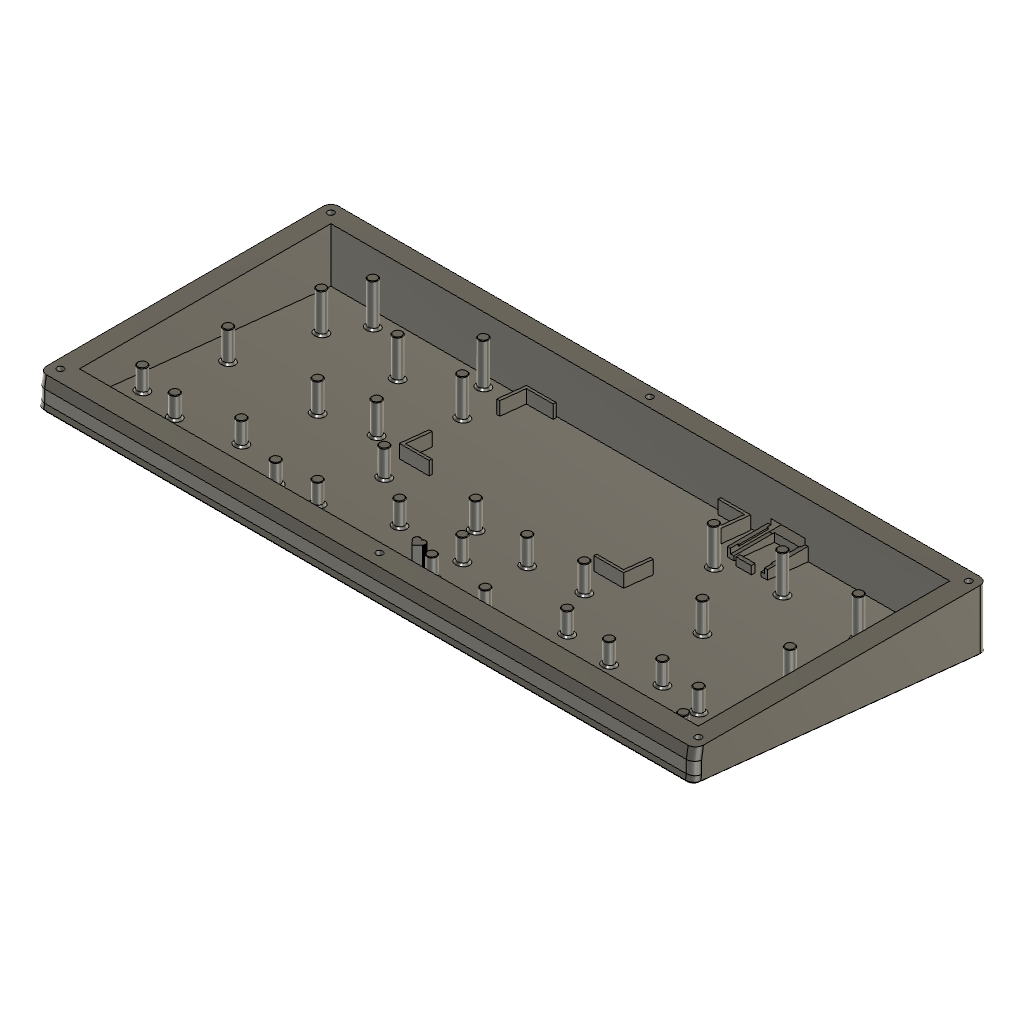
Bottom (Autodesk Fusion 360 design; units mm, degrees)
part number: 2026-11-25-15-39-00-303
part number: 2026-11-25-15-39-00-644
Autodesk Fusion 360 part; units mm, degrees
ref_plane "WorkPlane1" through (-10, 0, 0) normal (1, 0, 0) x (0, 1, 0) in component "Bottom"
sketch "side_profile" plane through (-10, 0, 0) normal (1, 0, 0) x (0, 0, -1) in component "Bottom"
  line L0 (-10, 10) -> (22.475, 10)
  line L1 (22.475, 10) -> (6.195, -144.863)
  line L2 (6.195, -144.863) -> (2.5, -144.25)
  line L3 (2.5, -144.25) -> (-4, -144.25)
  line L4 (-4, -144.25) -> (-10, -143.32)
  line L5 (-10, -143.32) -> (-10, 10)
extrude "Extrude1" add sketch "side_profile" along normal blind 344.85 makes body 1 in component "Bottom"
ref_plane "WorkPlane2" through (0, 0, -30) normal (0, 0, 1) x (1, 0, 0) in component "Bottom"
sketch "plan_outline" plane through (0, 0, -30) normal (0, 0, 1) x (1, 0, 0) in component "Bottom"
  line L0 (-10, -150) -> (334.85, -150)
  line L1 (334.85, -150) -> (334.85, 10)
  line L2 (334.85, 10) -> (-10, 10)
  line L3 (-10, 10) -> (-10, -150)
extrude "Extrude2" add sketch "plan_outline" along normal blind 50 separate body makes body 2 in component "Bottom"
fillet "Fillet1" radius 4 4 edges at (-10, 10, -5) (334.85, 10, -5) (334.85, -150, -5) (-10, -150, -5) on bodies 2 in component "Bottom"
combine "Combine1" operation intersect target body 1 tool bodies 2 in component "Bottom"
fillet "Front corner radius" radius 4 6 edges at (-10, -144.5565, -4.3475) (-10, -144.25, 0.75) (-10, -143.785, 7) (334.85, -144.5565, -4.3475) (334.85, -144.25, 0.75) (334.85, -143.785, 7) on bodies 1 in component "Bottom"
chamfer "Bottom edge chamfer" distance 1 angle 45 8 edges at (333.6784, -143.6958, -6.3177) (334.85, -67.4389, -14.3342) (333.6784, 8.8284, -22.3518) (162.425, 10, -22.475) (-8.8284, 8.8284, -22.3518) (-10, -67.4389, -14.3342) (-8.8284, -143.6958, -6.3177) (162.425, -144.863, -6.195) on bodies 1 in component "Bottom"
ref_plane "WorkPlane3" through (0, 0, 0) normal (1, 0, 0) x (0, 1, 0) in component "Bottom"
sketch "cavity_profile" plane through (0, 0, 0) normal (1, 0, 0) x (0, 0, -1) in component "Bottom"
  line L0 (-12, 0) -> (18.4216, 0)
  line L1 (18.4216, 0) -> (4.5516, -131.97)
  line L2 (4.5516, -131.97) -> (-12, -131.97)
  line L3 (-12, -131.97) -> (-12, 0)
extrude "Extrude3" cut sketch "cavity_profile" along normal blind 324.85 bodies 1 in component "Bottom"
ref_plane "WorkPlane4" through (0, 0, 10) normal (0, 0, 1) x (1, 0, 0) in component "Bottom"
sketch "screw_holes" plane through (0, 0, 10) normal (0, 0, 1) x (1, 0, 0) in component "Bottom"
  circle A0 centre (-5, 5) radius 1.7
  circle A1 centre (162.43, 5) radius 1.7
  circle A2 centre (329.85, 5) radius 1.7
  circle A3 centre (-5, -136.97) radius 1.7
  circle A4 centre (162.43, -136.97) radius 1.7
  circle A5 centre (329.85, -136.97) radius 1.7
  dimension "d27" = 3.4
  dimension "d28" = 3.4
  dimension "d29" = 3.4
  dimension "d30" = 3.4
  dimension "d31" = 3.4
  dimension "d32" = 3.4
  measures "d27" diameter of A0
  measures "d28" diameter of A1
  measures "d29" diameter of A2
  measures "d30" diameter of A3
  measures "d31" diameter of A4
  measures "d32" diameter of A5
ref_plane "WorkPlane5" through (0, 0, -3.7) normal (0, 0, 1) x (1, 0, 0) in component "Bottom"
sketch "counterbores_front" plane through (0, 0, -3.7) normal (0, 0, 1) x (1, 0, 0) in component "Bottom"
  circle A0 centre (-5, -136.97) radius 3
  circle A1 centre (162.43, -136.97) radius 3
  circle A2 centre (329.85, -136.97) radius 3
  dimension "d36" = 6
  dimension "d37" = 6
  dimension "d38" = 6
  measures "d36" diameter of A0
  measures "d37" diameter of A1
  measures "d38" diameter of A2
extrude "Counterbore front" cut sketch "counterbores_front" against normal blind 15 bodies 1 in component "Bottom"
ref_plane "WorkPlane6" through (0, 0, -17) normal (0, 0, 1) x (1, 0, 0) in component "Bottom"
sketch "counterbores_back" plane through (0, 0, -17) normal (0, 0, 1) x (1, 0, 0) in component "Bottom"
  circle A0 centre (-5, 5) radius 3
  circle A1 centre (162.43, 5) radius 3
  circle A2 centre (329.85, 5) radius 3
  dimension "d42" = 6
  dimension "d43" = 6
  dimension "d44" = 6
  measures "d42" diameter of A0
  measures "d43" diameter of A1
  measures "d44" diameter of A2
extrude "Counterbore back" cut sketch "counterbores_back" against normal blind 15 bodies 1 in component "Bottom"
sketch "foot_recesses" plane through (0, -2.2276, -21.1896) normal (0, -0.1045, -0.9945) x (0, 0.9945, -0.1045) in component "Bottom"
  circle A0 centre (-127.3101, 16) radius 6.665
  circle A1 centre (-3.6022, 16) radius 6.665
  circle A2 centre (-127.3101, 308.85) radius 6.665
  circle A3 centre (-3.6022, 308.85) radius 6.665
  ellipse E0 centre (-135.4849, 329.85) end of major axis (-138.5015, 329.85) minor radius 3
  ellipse E1 centre (-135.4849, 162.43) end of major axis (-138.5015, 162.43) minor radius 3
  ellipse E2 centre (-135.4849, -5) end of major axis (-138.5015, -5) minor radius 3
  ellipse E3 centre (7.2674, 329.85) end of major axis (4.2509, 329.85) minor radius 3
  ellipse E4 centre (7.2674, 162.43) end of major axis (4.2509, 162.43) minor radius 3
  ellipse E5 centre (7.2674, -5) end of major axis (4.2509, -5) minor radius 3
  line L0 (-139.3546, -9) -> (8.1678, -9)
  line L1 (8.2729, -9) -> (8.1678, -9)
  spline S0 degree 3 poles (11.2949, -6) (11.2949, -6.4845) (11.1745, -6.9686) (10.8063, -7.6628) (10.6252, -7.907) (10.4117, -8.1194) (10.1982, -8.3317) (9.9523, -8.5121) (9.2521, -8.8794) (8.7627, -9) (8.2729, -9) knots 0 0 0 0 0.485394 0.485394 0.785398 0.785398 0.785398 1.085403 1.085403 1.570796 1.570796 1.570796 1.570796
  line L2 (11.2949, -6) -> (11.2949, 330.85)
  spline S1 degree 3 poles (8.2729, 333.85) (8.7627, 333.85) (9.2521, 333.7294) (9.9523, 333.3621) (10.1982, 333.1817) (10.4117, 332.9694) (10.6252, 332.757) (10.8063, 332.5128) (11.1745, 331.8186) (11.2949, 331.3345) (11.2949, 330.85) knots -1.570796 -1.570796 -1.570796 -1.570796 -1.085403 -1.085403 -0.785398 -0.785398 -0.785398 -0.485394 -0.485394 0 0 0 0
  line L3 (8.1678, 333.85) -> (8.2729, 333.85)
  line L4 (8.1678, 333.85) -> (-139.3546, 333.85)
  line L5 (-139.4143, 333.85) -> (-139.3546, 333.85)
  spline S2 degree 3 poles (-142.4214, 330.85) (-142.4214, 331.3351) (-142.3012, 331.8198) (-141.9342, 332.5143) (-141.7539, 332.7585) (-141.5413, 332.9707) (-141.3287, 333.1829) (-141.084, 333.363) (-140.3875, 333.7298) (-139.9011, 333.85) (-139.4143, 333.85) knots 0 0 0 0 0.485398 0.485398 0.785398 0.785398 0.785398 1.085399 1.085399 1.570796 1.570796 1.570796 1.570796
  line L6 (-142.4214, 330.85) -> (-142.4214, -6)
  spline S3 degree 3 poles (-139.4143, -9) (-139.9011, -9) (-140.3875, -8.8798) (-141.084, -8.513) (-141.3287, -8.3329) (-141.5413, -8.1207) (-141.7539, -7.9085) (-141.9342, -7.6643) (-142.3012, -6.9698) (-142.4214, -6.4851) (-142.4214, -6) knots -1.570796 -1.570796 -1.570796 -1.570796 -1.085399 -1.085399 -0.785398 -0.785398 -0.785398 -0.485398 -0.485398 0 0 0 0
  line L7 (-139.3546, -9) -> (-139.4143, -9)
  dimension "d46" = 13.33
  dimension "d47" = 13.33
  dimension "d48" = 13.33
  dimension "d49" = 13.33
  measures "d46" diameter of A0
  measures "d47" diameter of A1
  measures "d48" diameter of A2
  measures "d49" diameter of A3
extrude "Extrude7" cut sketch "foot_recesses" against normal blind 1 contours A0 | A1 | A2 | A3 bodies 1 in component "Bottom"
ref_plane "WorkPlane7" through (0, 0, 5) normal (0, 0, 1) x (1, 0, 0) in component "Bottom"
sketch "support_posts" plane through (0, 0, 5) normal (0, 0, 1) x (1, 0, 0) in component "Bottom"
  circle A0 centre (170.5, -101.469) radius 2.5
  circle A1 centre (307.501, -66.469) radius 2.5
  circle A2 centre (30.501, -112.469) radius 2.5
  circle A3 centre (261.501, -24.469) radius 2.5
  circle A4 centre (301.501, -24.469) radius 2.5
  circle A5 centre (109.501, -81.469) radius 2.5
  circle A6 centre (309.501, -124.469) radius 2.5
  circle A7 centre (231.5, -30.469) radius 2.5
  circle A8 centre (97.501, -28.469) radius 2.5
  circle A9 centre (87.501, -116.469) radius 2.5
  circle A10 centre (107.501, -114.469) radius 2.5
  circle A11 centre (86.501, -62.469) radius 2.5
  circle A12 centre (9.501, -108.469) radius 2.5
  circle A13 centre (30.501, -8.469) radius 2.5
  circle A14 centre (187.501, -84.469) radius 2.5
  circle A15 centre (86.501, -6.469) radius 2.5
  circle A16 centre (231.501, -107.469) radius 2.5
  circle A17 centre (301.501, -108.469) radius 2.5
  circle A18 centre (21.501, -26.469) radius 2.5
  circle A19 centre (279.501, -105.469) radius 2.5
  circle A20 centre (171.501, -118.469) radius 2.5
  circle A21 centre (61.501, -68.469) radius 2.5
  circle A22 centre (137.5, -101.469) radius 2.5
  circle A23 centre (214.5, -81.469) radius 2.5
  circle A24 centre (62.501, -27.469) radius 2.5
  circle A25 centre (262.501, -67.469) radius 2.5
  circle A26 centre (14.501, -68.469) radius 2.5
  circle A27 centre (200.5, -119.469) radius 2.5
  circle A28 centre (59.501, -106.469) radius 2.5
  circle A29 centre (256.501, -110.469) radius 2.5
  circle A30 centre (157.501, -81.469) radius 2.5
  line L0 (162.501, -119.911) -> (159.835, -117.119)
  line L1 (159.835, -117.119) -> (159.647, -116.885)
  line L2 (159.647, -116.885) -> (159.502, -116.623)
  line L3 (159.502, -116.623) -> (159.404, -116.339)
  line L4 (159.404, -116.339) -> (159.356, -116.043)
  line L5 (159.356, -116.043) -> (159.359, -115.743)
  line L6 (159.359, -115.743) -> (159.413, -115.448)
  line L7 (159.413, -115.448) -> (159.516, -115.167)
  line L8 (159.516, -115.167) -> (159.667, -114.907)
  line L9 (159.667, -114.907) -> (159.859, -114.677)
  line L10 (159.859, -114.677) -> (160.088, -114.483)
  line L11 (160.088, -114.483) -> (160.346, -114.331)
  line L12 (160.346, -114.331) -> (160.627, -114.226)
  line L13 (160.627, -114.226) -> (160.764, -114.2)
  line L14 (160.764, -114.2) -> (160.922, -114.17)
  line L15 (160.922, -114.17) -> (161.222, -114.165)
  line L16 (161.222, -114.165) -> (161.518, -114.211)
  line L17 (161.518, -114.211) -> (161.802, -114.307)
  line L18 (161.802, -114.307) -> (161.943, -114.384)
  line L19 (161.943, -114.384) -> (162.066, -114.45)
  line L20 (162.066, -114.45) -> (162.301, -114.637)
  line L21 (162.301, -114.637) -> (162.501, -114.86)
  line L22 (162.501, -114.86) -> (162.7, -114.637)
  line L23 (162.7, -114.637) -> (162.935, -114.45)
  line L24 (162.935, -114.45) -> (163.058, -114.384)
  line L25 (163.058, -114.384) -> (163.199, -114.307)
  line L26 (163.199, -114.307) -> (163.483, -114.211)
  line L27 (163.483, -114.211) -> (163.779, -114.165)
  line L28 (163.779, -114.165) -> (164.079, -114.17)
  line L29 (164.079, -114.17) -> (164.237, -114.2)
  line L30 (164.237, -114.2) -> (164.374, -114.226)
  line L31 (164.374, -114.226) -> (164.655, -114.331)
  line L32 (164.655, -114.331) -> (164.913, -114.483)
  line L33 (164.913, -114.483) -> (165.142, -114.677)
  line L34 (165.142, -114.677) -> (165.334, -114.907)
  line L35 (165.334, -114.907) -> (165.414, -115.045)
  line L36 (165.414, -115.045) -> (165.485, -115.167)
  line L37 (165.485, -115.167) -> (165.588, -115.448)
  line L38 (165.588, -115.448) -> (165.643, -115.743)
  line L39 (165.643, -115.743) -> (165.645, -116.043)
  line L40 (165.645, -116.043) -> (165.597, -116.339)
  line L41 (165.597, -116.339) -> (165.499, -116.623)
  line L42 (165.499, -116.623) -> (165.354, -116.885)
  line L43 (165.354, -116.885) -> (165.166, -117.119)
  line L44 (165.166, -117.119) -> (162.501, -119.911)
  dimension "d58" = 5
  dimension "d59" = 5
  dimension "d60" = 5
  dimension "d61" = 5
  dimension "d62" = 5
  dimension "d63" = 5
  dimension "d64" = 5
  dimension "d65" = 5
  dimension "d66" = 5
  dimension "d67" = 5
  dimension "d68" = 5
  dimension "d69" = 5
  dimension "d70" = 5
  dimension "d71" = 5
  dimension "d72" = 5
  dimension "d73" = 5
  dimension "d74" = 5
  dimension "d75" = 5
  dimension "d76" = 5
  dimension "d77" = 5
  dimension "d78" = 5
  dimension "d79" = 5
  dimension "d80" = 5
  dimension "d81" = 5
  dimension "d82" = 5
  dimension "d83" = 5
  dimension "d84" = 5
  dimension "d85" = 5
  dimension "d86" = 5
  dimension "d87" = 5
  dimension "d88" = 5
  measures "d58" diameter of A0
  measures "d59" diameter of A1
  measures "d60" diameter of A2
  measures "d61" diameter of A3
  measures "d62" diameter of A4
  measures "d63" diameter of A5
  measures "d64" diameter of A6
  measures "d65" diameter of A7
  measures "d66" diameter of A8
  measures "d67" diameter of A9
  measures "d68" diameter of A10
  measures "d69" diameter of A11
  measures "d70" diameter of A12
  measures "d71" diameter of A13
  measures "d72" diameter of A14
  measures "d73" diameter of A15
  measures "d74" diameter of A16
  measures "d75" diameter of A17
  measures "d76" diameter of A18
  measures "d77" diameter of A19
  measures "d78" diameter of A20
  measures "d79" diameter of A21
  measures "d80" diameter of A22
  measures "d81" diameter of A23
  measures "d82" diameter of A24
  measures "d83" diameter of A25
  measures "d84" diameter of A26
  measures "d85" diameter of A27
  measures "d86" diameter of A28
  measures "d87" diameter of A29
  measures "d88" diameter of A30
extrude "Posts" add sketch "support_posts" along normal up to surface end surface through (0, 0, -18.4216) normal (0, 0.104524, 0.994522) offset 0 bodies 1 in component "Bottom"
chamfer "Post top chamfer" distance 0.3 angle 45 31 edges at (254.1702, -111.373, 5) (198.1692, -120.373, 5) (260.1702, -68.373, 5) (212.1692, -82.373, 5) (59.1702, -69.373, 5) (277.1702, -106.373, 5) (299.1702, -109.373, 5) (168.1692, -102.373, 5) (185.1702, -85.373, 5) (7.1702, -109.373, 5) (105.1702, -115.373, 5) (95.1702, -29.373, 5) (307.1702, -125.373, 5) (299.1702, -25.373, 5) (28.1702, -113.373, 5) (305.1702, -67.373, 5) (259.1702, -25.373, 5) (107.1702, -82.373, 5) (229.1692, -31.373, 5) (85.1702, -117.373, 5) (84.1702, -63.373, 5) (28.1702, -9.373, 5) (84.1702, -7.373, 5) (229.1702, -108.373, 5) (19.1702, -27.373, 5) (169.1702, -119.373, 5) (135.1692, -102.373, 5) (60.1702, -28.373, 5) (12.1702, -69.373, 5) (57.1702, -107.373, 5) (155.1702, -82.373, 5) on bodies 1 in component "Bottom"
chamfer "Post base chamfer" distance 1 angle 45 31 edges at (157.501, -78.969, -10.122) (59.501, -103.969, -7.4945) (14.501, -65.969, -11.4883) (62.501, -24.969, -15.7974) (137.5, -98.969, -8.02) (171.501, -115.969, -6.2333) (21.501, -23.969, -15.9025) (231.501, -104.969, -7.3894) (86.501, -3.969, -18.0045) (30.501, -5.969, -17.7943) (86.501, -59.969, -12.1189) (87.501, -113.969, -6.4435) (231.5, -27.969, -15.4821) (109.501, -78.969, -10.122) (261.501, -21.969, -16.1127) (307.501, -63.969, -11.6985) (30.501, -109.969, -6.8639) (301.501, -21.969, -16.1127) (309.501, -121.969, -5.6027) (97.501, -25.969, -15.6923) (107.501, -111.969, -6.6537) (9.501, -105.969, -7.2843) (187.501, -81.969, -9.8067) (170.5, -98.969, -8.02) (301.501, -105.969, -7.2843) (279.501, -102.969, -7.5996) (61.501, -65.969, -11.4883) (214.5, -78.969, -10.122) (262.501, -64.969, -11.5934) (200.5, -116.969, -6.1282) (256.501, -107.969, -7.0741) on bodies 1 in component "Bottom"
ref_plane "WorkPlane8" through (162.425, -65.2533, -4.5249) normal (0, 0.1045, 0.9945) x (0, -0.9945, 0.1045) in component "Bottom"
ref_plane "WorkPlane9" through (0, 0, -14) normal (0, 0, 1) x (1, 0, 0) in component "Bottom"
sketch "charger_rails" plane through (0, 0, -14) normal (0, 0, 1) x (1, 0, 0) in component "Bottom"
  line L0 (231.05, -21.3) -> (232.85, -21.3)
  line L1 (232.85, -21.3) -> (232.85, 0.5)
  line L2 (232.85, 0.5) -> (231.05, 0.5)
  line L3 (231.05, 0.5) -> (231.05, -21.3)
  line L4 (247.15, -21.3) -> (248.95, -21.3)
  line L5 (248.95, -21.3) -> (248.95, 0.5)
  line L6 (248.95, 0.5) -> (247.15, 0.5)
  line L7 (247.15, 0.5) -> (247.15, -21.3)
extrude "Charger rails" add sketch "charger_rails" along normal up to surface end surface through (0, 0, -18.4216) normal (0, 0.104524, 0.994522) offset 0 bodies 1 in component "Bottom"
ref_plane "WorkPlane10" through (0, 0, -11.4) normal (0, 0, 1) x (1, 0, 0) in component "Bottom"
sketch "charger_guides" plane through (0, 0, -11.4) normal (0, 0, 1) x (1, 0, 0) in component "Bottom"
  line L0 (229.45, -21.3) -> (231.05, -21.3)
  line L1 (231.05, -21.3) -> (231.05, 0.5)
  line L2 (231.05, 0.5) -> (229.45, 0.5)
  line L3 (229.45, 0.5) -> (229.45, -21.3)
  line L4 (248.95, -21.3) -> (250.55, -21.3)
  line L5 (250.55, -21.3) -> (250.55, 0.5)
  line L6 (250.55, 0.5) -> (248.95, 0.5)
  line L7 (248.95, 0.5) -> (248.95, -21.3)
extrude "Charger guides" add sketch "charger_guides" along normal up to surface end surface through (0, 0, -18.4216) normal (0, 0.104524, 0.994522) offset 0 bodies 1 in component "Bottom"
ref_plane "WorkPlane11" through (0, 0, -11.8) normal (0, 0, 1) x (1, 0, 0) in component "Bottom"
sketch "charger_rear_stop" plane through (0, 0, -11.8) normal (0, 0, 1) x (1, 0, 0) in component "Bottom"
  line L0 (236, -23.3) -> (244, -23.3)
  line L1 (244, -23.3) -> (244, -21.3)
  line L2 (244, -21.3) -> (236, -21.3)
  line L3 (236, -21.3) -> (236, -23.3)
extrude "Charger rear stop" add sketch "charger_rear_stop" along normal up to surface end surface through (0, 0, -18.4216) normal (0, 0.104524, 0.994522) offset 0 bodies 1 in component "Bottom"
sketch "charger_snap_lips" plane through (0, 0, -11.4) normal (0, 0, 1) x (1, 0, 0) in component "Bottom"
  line L0 (231.05, -17.3) -> (231.55, -17.3)
  line L1 (231.55, -17.3) -> (231.55, -2)
  line L2 (231.55, -2) -> (231.05, -2)
  line L3 (231.05, -2) -> (231.05, -17.3)
  line L4 (248.45, -17.3) -> (248.95, -17.3)
  line L5 (248.95, -17.3) -> (248.95, -2)
  line L6 (248.95, -2) -> (248.45, -2)
  line L7 (248.45, -2) -> (248.45, -17.3)
extrude "Charger snap lips" add sketch "charger_snap_lips" against normal blind 0.8 bodies 1 in component "Bottom"
ref_plane "WorkPlane12" through (0, 0, -14.01) normal (0, 0, 1) x (1, 0, 0) in component "Bottom"
sketch "charger_wall_pocket" plane through (0, 0, -14.01) normal (0, 0, 1) x (1, 0, 0) in component "Bottom"
  line L0 (231.05, -1) -> (248.95, -1)
  line L1 (248.95, -1) -> (248.95, 8.3)
  line L2 (248.95, 8.3) -> (231.05, 8.3)
  line L3 (231.05, 8.3) -> (231.05, -1)
extrude "Charger wall pocket" cut sketch "charger_wall_pocket" along normal blind 5.41 bodies 1 in component "Bottom"
ref_plane "WorkPlane13" through (0, 8, 0) normal (0, 1, 0) x (0, 0, 1) in component "Bottom"
sketch "usbc_slot" plane through (0, 8, 0) normal (0, 1, 0) x (1, 0, 0) in component "Bottom"
  line L0 (237.2, 9.27) -> (242.8, 9.27)
  line L1 (237.2, 13.07) -> (242.8, 13.07)
  arc A0 (242.8, 9.27) -> (242.8, 13.07) centre (242.8, 11.17) ccw
  arc A1 (237.2, 13.07) -> (237.2, 9.27) centre (237.2, 11.17) ccw
extrude "USB-C slot" cut sketch "usbc_slot" along normal blind 3 bodies 1 in component "Bottom"
extrude "Screw holes" cut sketch "screw_holes" against normal blind 35 bodies 1 in component "Bottom"
ref_plane "WorkPlane14" through (0, 0, -3) normal (0, 0, 1) x (1, 0, 0) in component "Bottom"
sketch "battery_brackets" plane through (0, 0, -3) normal (0, 0, 1) x (1, 0, 0) in component "Bottom"
  line L0 (103.5755, -67.6) -> (119.1755, -67.6)
  line L1 (119.1755, -67.6) -> (119.1755, -66)
  line L2 (119.1755, -66) -> (105.1755, -66)
  line L3 (105.1755, -66) -> (105.1755, -52)
  line L4 (105.1755, -52) -> (103.5755, -52)
  line L5 (103.5755, -52) -> (103.5755, -67.6)
  line L6 (221.2755, -67.6) -> (205.6755, -67.6)
  line L7 (205.6755, -67.6) -> (205.6755, -66)
  line L8 (205.6755, -66) -> (219.6755, -66)
  line L9 (219.6755, -66) -> (219.6755, -52)
  line L10 (219.6755, -52) -> (221.2755, -52)
  line L11 (221.2755, -52) -> (221.2755, -67.6)
  line L12 (103.5755, -0.9) -> (119.1755, -0.9)
  line L13 (119.1755, -0.9) -> (119.1755, -2.5)
  line L14 (119.1755, -2.5) -> (105.1755, -2.5)
  line L15 (105.1755, -2.5) -> (105.1755, -16.5)
  line L16 (105.1755, -16.5) -> (103.5755, -16.5)
  line L17 (103.5755, -16.5) -> (103.5755, -0.9)
  line L18 (221.2755, -0.9) -> (205.6755, -0.9)
  line L19 (205.6755, -0.9) -> (205.6755, -2.5)
  line L20 (205.6755, -2.5) -> (219.6755, -2.5)
  line L21 (219.6755, -2.5) -> (219.6755, -16.5)
  line L22 (219.6755, -16.5) -> (221.2755, -16.5)
  line L23 (221.2755, -16.5) -> (221.2755, -0.9)
extrude "Battery brackets" add sketch "battery_brackets" along normal up to surface start surface through (162.425, -65.2533, -4.5249) normal (0, 0.104524, 0.994522) end surface through (0, 0, -18.4216) normal (0, 0.104524, 0.994522) offset 0 bodies 1 in component "Bottom"
component "Bottom" placed x (1, 0, 0) y (0, 1, 0) z (0, 0, 1) at (0, 0, 0)
equation "case_len = 344.85 mm" comment "outer length X"
equation "corner_r = 4 mm" comment "outer vertical corner radius"
equation "bottom_chamfer = 1 mm" comment "bottom edge chamfer"
equation "screw_d = 3.4 mm" comment "screw clearance hole"
equation "cbore_d = 6 mm" comment "screw counterbore"
equation "foot_d = 13.33 mm" comment "rubber foot recess dia"
equation "foot_depth = 1 mm" comment "rubber foot recess depth"
equation "d10 = case_len"
equation "d17 = corner_r"
equation "floor_z_back = -18.4216 mm" comment "floor height at the back wall (y=0)"
equation "floor_z_front = -4.5516 mm" comment "floor height at the front wall (y=-131.97), 6 deg slope"
equation "d27 = screw_d"
equation "d28 = screw_d"
equation "d29 = screw_d"
equation "d30 = screw_d"
equation "d31 = screw_d"
equation "d32 = screw_d"
equation "d36 = cbore_d"
equation "d37 = cbore_d"
equation "d38 = cbore_d"
equation "d42 = cbore_d"
equation "d43 = cbore_d"
equation "d44 = cbore_d"
equation "d46 = foot_d"
equation "d47 = foot_d"
equation "d48 = foot_d"
equation "d49 = foot_d"
equation "d50 = -( foot_depth )"
equation "pcb_underside_z = 5 mm" comment "post top = PCB underside"
equation "post_d = 5 mm" comment "support post diameter"
equation "post_top_chamfer = 0.3 mm" comment "post top chamfer"
equation "post_base_chamfer = 1 mm" comment "post-to-floor chamfer (replaces tapered base)"
equation "d56 = pcb_underside_z"
equation "d58 = post_d"
equation "d59 = post_d"
equation "d60 = post_d"
equation "d61 = post_d"
equation "d62 = post_d"
equation "d63 = post_d"
equation "d64 = post_d"
equation "d65 = post_d"
equation "d66 = post_d"
equation "d67 = post_d"
equation "d68 = post_d"
equation "d69 = post_d"
equation "d70 = post_d"
equation "d71 = post_d"
equation "d72 = post_d"
equation "d73 = post_d"
equation "d74 = post_d"
equation "d75 = post_d"
equation "d76 = post_d"
equation "d77 = post_d"
equation "d78 = post_d"
equation "d79 = post_d"
equation "d80 = post_d"
equation "d81 = post_d"
equation "d82 = post_d"
equation "d83 = post_d"
equation "d84 = post_d"
equation "d85 = post_d"
equation "d86 = post_d"
equation "d87 = post_d"
equation "d88 = post_d"
equation "d91 = post_top_chamfer"
equation "d92 = post_base_chamfer"
equation "bat_bracket_h = 7 mm" comment "battery corner bracket height above floor"
equation "d94 = bat_bracket_h"
equation "d110 = -( 0.80 mm )"
equation "usbc_w = 9.4 mm" comment "USB-C opening width"
equation "usbc_h = 3.8 mm" comment "USB-C opening height"
equation "d122 = -( 35.00 mm )"
equation "d124 = -( 15.00 mm )"
equation "d125 = -( 15.00 mm )"
equation "d132 = corner_r"
equation "d133 = bottom_chamfer"
named bodies: "Bottom"
